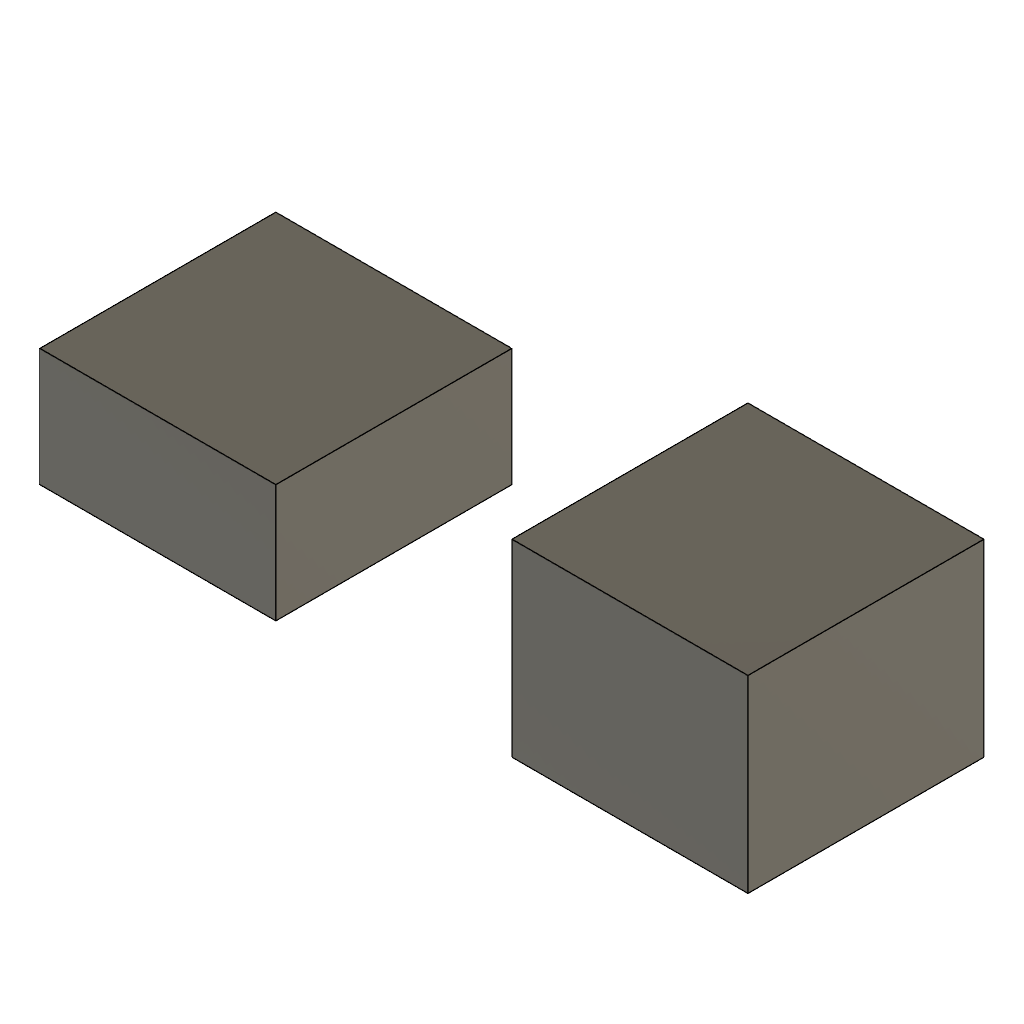
copy_paste_two_components (Autodesk Fusion 360 design; units mm, degrees)
Autodesk Fusion 360 part; units mm, degrees
sketch "Sketch1" plane through (0, 0, 0) normal (0, 0, 1) x (1, 0, 0) in component "A"
  line L0 (0, 0) -> (10, 0)
  line L1 (10, 0) -> (10, 10)
  line L2 (10, 10) -> (0, 10)
  line L3 (0, 10) -> (0, 0)
extrude "Extrude1" add sketch "Sketch1" along normal blind 5 makes body 1 in component "A"
sketch "Sketch1 (2)" plane through (0, 0, 0) normal (0, 0, 1) x (1, 0, 0) in component "B"
  line L0 (0, 0) -> (10, 0)
  line L1 (10, 0) -> (10, 10)
  line L2 (10, 10) -> (0, 10)
  line L3 (0, 10) -> (0, 0)
extrude "Extrude1'" add sketch "Sketch1 (2)" along normal blind 8 separate body makes body 2 in component "B"
copy_body "CopyPasteBodies1" bodies 1 2 body 1 seen with x (1, 0, 0) y (0, 1, 0) z (0, 0, 1) at (0, -30, 0) body 2 seen with x (1, 0, 0) y (0, 1, 0) z (0, 0, 1) at (20, -30, 0) makes body 3 makes body 4 in component "Target"
component "A" placed x (1, 0, 0) y (0, 1, 0) z (0, 0, 1) at (0, 0, 0)
component "B" placed x (1, 0, 0) y (0, 1, 0) z (0, 0, 1) at (20, 0, 0)
component "Target" placed x (1, 0, 0) y (0, 1, 0) z (0, 0, 1) at (0, 30, 0)
